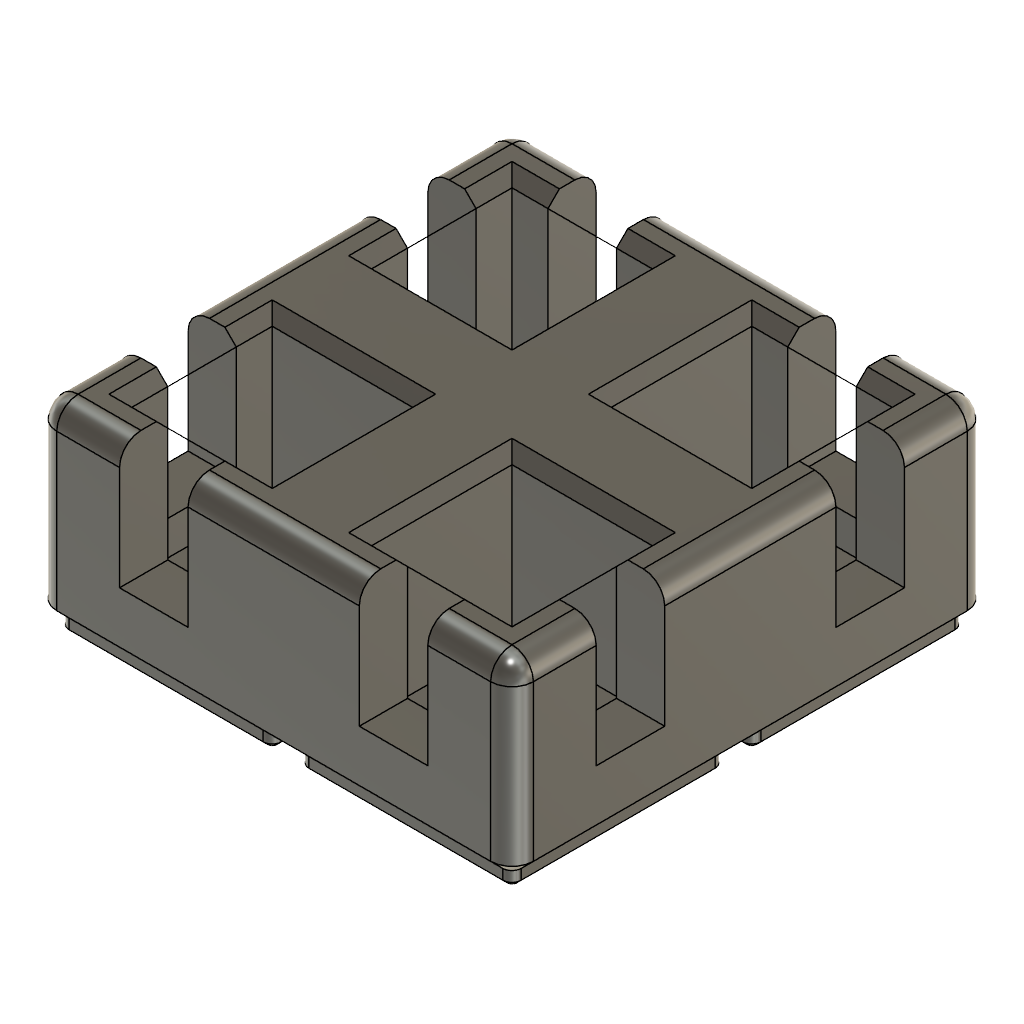
ready-parts-input-holder-v2 (Autodesk Fusion 360 design; units mm, degrees)
part number: 2026-10-03-11-04-50-135
Autodesk Fusion 360 part; units mm, degrees
sketch "Sketch_OuterProfile" plane through (0, 0, 0) normal (0, 0, 1) x (1, 0, 0)
  line L0 (41.75, 41.75) -> (-41.75, 41.75)
  line L1 (-41.75, 41.75) -> (-41.75, -41.75)
  line L2 (-41.75, -41.75) -> (41.75, -41.75)
  line L3 (41.75, -41.75) -> (41.75, 41.75)
  line L4 (41.75, 41.75) -> (-41.75, -41.75) construction
  dimension "d24" = 83.5
  dimension "d25" = 83.5
  constraint midpoint origin L4
  measures "d24" horizontal distance of L0.start L0.end
  measures "d25" vertical distance of L0.end L1.end
extrude "Extrude_Body" add sketch "Sketch_OuterProfile" along normal blind 31
fillet "Fillet_OuterVerticalEdges" radius 3.75 4 edges at (41.75, -41.75, 15.5) (-41.75, -41.75, 15.5) (-41.75, 41.75, 15.5) (41.75, 41.75, 15.5)
fillet "Fillet_TopOuterEdge" radius 3.75 64 edges at (40.6517, 40.6517, 31) (41.75, 0, 31) (40.6517, -40.6517, 31) (0, -41.75, 31) (-40.6517, -40.6517, 31) (-41.75, 0, 31) (-40.6517, 40.6517, 31) (0, 41.75, 31) (0, 41.75, 31) (-40.6517, 40.6517, 31) (-41.75, 0, 31) (-40.6517, -40.6517, 31) (0, -41.75, 31) (40.6517, -40.6517, 31) (41.75, 0, 31) (40.6517, 40.6517, 31) (-40.6517, 40.6517, 31) (0, 41.75, 31) (40.6517, 40.6517, 31) (41.75, 0, 31) (40.6517, -40.6517, 31) (0, -41.75, 31) (-40.6517, -40.6517, 31) (-41.75, 0, 31) (-41.75, 0, 31) (-40.6517, -40.6517, 31) (0, -41.75, 31) (40.6517, -40.6517, 31) (41.75, 0, 31) (40.6517, 40.6517, 31) (0, 41.75, 31) (-40.6517, 40.6517, 31) (-40.6517, -40.6517, 31) (-41.75, 0, 31) (-40.6517, 40.6517, 31) (0, 41.75, 31) (40.6517, 40.6517, 31) (41.75, 0, 31) (40.6517, -40.6517, 31) (0, -41.75, 31) (0, -41.75, 31) (40.6517, -40.6517, 31) (41.75, 0, 31) (40.6517, 40.6517, 31) (0, 41.75, 31) (-40.6517, 40.6517, 31) (-41.75, 0, 31) (-40.6517, -40.6517, 31) (40.6517, -40.6517, 31) (0, -41.75, 31) (-40.6517, -40.6517, 31) (-41.75, 0, 31) (-40.6517, 40.6517, 31) (0, 41.75, 31) (40.6517, 40.6517, 31) (41.75, 0, 31) (41.75, 0, 31) (40.6517, 40.6517, 31) (0, 41.75, 31) (-40.6517, 40.6517, 31) (-41.75, 0, 31) (-40.6517, -40.6517, 31) (0, -41.75, 31) (40.6517, -40.6517, 31)
ref_plane "WorkPlane1" through (0, 0, 11) normal (0, 0, 1) x (1, 0, 0)
sketch "Sketch_Pocket_1" plane through (0, 0, 11) normal (0, 0, 1) x (1, 0, 0)
  line L0 (-8.7, -8.7) -> (-33.3, -8.7)
  line L1 (-33.3, -8.7) -> (-33.3, -33.3)
  line L2 (-33.3, -33.3) -> (-8.7, -33.3)
  line L3 (-8.7, -33.3) -> (-8.7, -8.7)
  dimension "d35" = 24.6
  dimension "d36" = 24.6
  measures "d35" horizontal distance of L0.start L0.end
  measures "d36" vertical distance of L0.end L1.end
extrude "Extrude_Pocket_1" cut sketch "Sketch_Pocket_1" along normal blind -8 and the other way blind -25
sketch "Sketch_Pocket_2" plane through (0, 0, 11) normal (0, 0, 1) x (1, 0, 0)
  line L0 (-8.7, 33.3) -> (-33.3, 33.3)
  line L1 (-33.3, 33.3) -> (-33.3, 8.7)
  line L2 (-33.3, 8.7) -> (-8.7, 8.7)
  line L3 (-8.7, 8.7) -> (-8.7, 33.3)
  dimension "d39" = 24.6
  dimension "d40" = 24.6
  measures "d39" horizontal distance of L0.start L0.end
  measures "d40" vertical distance of L0.end L1.end
extrude "Extrude_Pocket_2" cut sketch "Sketch_Pocket_2" along normal blind -8 and the other way blind -45
sketch "Sketch_Pocket_3" plane through (0, 0, 11) normal (0, 0, 1) x (1, 0, 0)
  line L0 (33.3, -8.7) -> (8.7, -8.7)
  line L1 (8.7, -8.7) -> (8.7, -33.3)
  line L2 (8.7, -33.3) -> (33.3, -33.3)
  line L3 (33.3, -33.3) -> (33.3, -8.7)
  dimension "d43" = 24.6
  dimension "d44" = 24.6
  measures "d43" horizontal distance of L0.start L0.end
  measures "d44" vertical distance of L0.end L1.end
extrude "Extrude_Pocket_3" cut sketch "Sketch_Pocket_3" along normal blind -8 and the other way blind -42
sketch "Sketch_Pocket_4" plane through (0, 0, 11) normal (0, 0, 1) x (1, 0, 0)
  line L0 (33.3, 33.3) -> (8.7, 33.3)
  line L1 (8.7, 33.3) -> (8.7, 8.7)
  line L2 (8.7, 8.7) -> (33.3, 8.7)
  line L3 (33.3, 8.7) -> (33.3, 33.3)
  dimension "d47" = 24.6
  dimension "d48" = 24.6
  measures "d47" horizontal distance of L0.start L0.end
  measures "d48" vertical distance of L0.end L1.end
extrude "Extrude_Pocket_4" cut sketch "Sketch_Pocket_4" along normal blind -8 and the other way blind -38
chamfer "Chamfer_PocketEdges" distance 2 angle 45 12 edges at (33.3, 21, 31) (8.7, 21, 31) (21, 33.3, 31) (33.3, -21, 31) (8.7, -21, 31) (21, -8.7, 31) (-8.7, 21, 31) (-33.3, 21, 31) (-21, 33.3, 31) (-8.7, -21, 31) (-33.3, -21, 31) (-21, -8.7, 31) tangent chain off
chamfer "Chamfer_PocketEdges" distance 2 angle 45 4 edges at (21, -33.3, 31) (-21, -33.3, 31) (-21, 8.7, 31) (21, 8.7, 31) tangent chain off
sketch "Sketch_Foot_1" plane through (0, 0, 0) normal (0, 0, 1) x (1, 0, 0)
  line L0 (-3.01, -3.01) -> (-38.99, -3.01)
  line L1 (-38.99, -3.01) -> (-38.99, -38.99)
  line L2 (-38.99, -38.99) -> (-3.01, -38.99)
  line L3 (-3.01, -38.99) -> (-3.01, -3.01)
  dimension "d61" = 35.98
  dimension "d62" = 35.98
  measures "d61" horizontal distance of L0.start L0.end
  measures "d62" vertical distance of L0.end L1.end
extrude "Extrude_Foot_1" [suppressed]
fillet "Fillet_FootEdges_1" [suppressed]
sketch "Sketch_Foot_2" plane through (0, 0, 0) normal (0, 0, 1) x (1, 0, 0)
  line L0 (-3.01, 38.99) -> (-38.99, 38.99)
  line L1 (-38.99, 38.99) -> (-38.99, 3.01)
  line L2 (-38.99, 3.01) -> (-3.01, 3.01)
  line L3 (-3.01, 3.01) -> (-3.01, 38.99)
  dimension "d67" = 35.98
  dimension "d68" = 35.98
  measures "d67" horizontal distance of L0.start L0.end
  measures "d68" vertical distance of L0.end L1.end
extrude "Extrude_Foot_2" [suppressed]
fillet "Fillet_FootEdges_2" [suppressed]
sketch "Sketch_Foot_3" plane through (0, 0, 0) normal (0, 0, 1) x (1, 0, 0)
  line L0 (38.99, -3.01) -> (3.01, -3.01)
  line L1 (3.01, -3.01) -> (3.01, -38.99)
  line L2 (3.01, -38.99) -> (38.99, -38.99)
  line L3 (38.99, -38.99) -> (38.99, -3.01)
  dimension "d73" = 35.98
  dimension "d74" = 35.98
  measures "d73" horizontal distance of L0.start L0.end
  measures "d74" vertical distance of L0.end L1.end
extrude "Extrude_Foot_3" [suppressed]
fillet "Fillet_FootEdges_3" [suppressed]
sketch "Sketch_Foot_4" plane through (0, 0, 0) normal (0, 0, 1) x (1, 0, 0)
  line L0 (38.99, 38.99) -> (3.01, 38.99)
  line L1 (3.01, 38.99) -> (3.01, 3.01)
  line L2 (3.01, 3.01) -> (38.99, 3.01)
  line L3 (38.99, 3.01) -> (38.99, 38.99)
  dimension "d79" = 35.98
  dimension "d80" = 35.98
  measures "d79" horizontal distance of L0.start L0.end
  measures "d80" vertical distance of L0.end L1.end
extrude "Extrude_Foot_4" [suppressed]
fillet "Fillet_FootEdges_4" [suppressed]
extrude "Extrude10" [suppressed]
ref_plane "WorkPlane2" through (0, 0, 0) normal (0, 0, 1) x (1, 0, 0)
sketch "gf_std_foot1" plane through (0, 0, 0) normal (0, 0, 1) x (1, 0, 0)
  line L0 (-4, -0.25) -> (-38, -0.25)
  line L1 (-41.75, -4) -> (-41.75, -38)
  line L2 (-38, -41.75) -> (-4, -41.75)
  line L3 (-0.25, -38) -> (-0.25, -4)
  arc A0 (-38, -0.25) -> (-41.75, -4) centre (-38, -4) ccw
  arc A1 (-41.75, -38) -> (-38, -41.75) centre (-38, -38) ccw
  arc A2 (-4, -41.75) -> (-0.25, -38) centre (-4, -38) ccw
  arc A3 (-0.25, -4) -> (-4, -0.25) centre (-4, -4) ccw
  line L4 (-4, 41.75) -> (-38, 41.75)
  line L5 (-41.75, 38) -> (-41.75, 4)
  line L6 (-38, 0.25) -> (-4, 0.25)
  line L7 (-0.25, 4) -> (-0.25, 38)
  arc A4 (-38, 41.75) -> (-41.75, 38) centre (-38, 38) ccw
  arc A5 (-41.75, 4) -> (-38, 0.25) centre (-38, 4) ccw
  arc A6 (-4, 0.25) -> (-0.25, 4) centre (-4, 4) ccw
  arc A7 (-0.25, 38) -> (-4, 41.75) centre (-4, 38) ccw
  line L8 (38, -0.25) -> (4, -0.25)
  line L9 (0.25, -4) -> (0.25, -38)
  line L10 (4, -41.75) -> (38, -41.75)
  line L11 (41.75, -38) -> (41.75, -4)
  arc A8 (4, -0.25) -> (0.25, -4) centre (4, -4) ccw
  arc A9 (0.25, -38) -> (4, -41.75) centre (4, -38) ccw
  arc A10 (38, -41.75) -> (41.75, -38) centre (38, -38) ccw
  arc A11 (41.75, -4) -> (38, -0.25) centre (38, -4) ccw
  line L12 (38, 41.75) -> (4, 41.75)
  line L13 (0.25, 38) -> (0.25, 4)
  line L14 (4, 0.25) -> (38, 0.25)
  line L15 (41.75, 4) -> (41.75, 38)
  arc A12 (4, 41.75) -> (0.25, 38) centre (4, 38) ccw
  arc A13 (0.25, 4) -> (4, 0.25) centre (4, 4) ccw
  arc A14 (38, 0.25) -> (41.75, 4) centre (38, 4) ccw
  arc A15 (41.75, 38) -> (38, 41.75) centre (38, 38) ccw
  constraint tangent L0 A0
  constraint tangent L1 A0
  constraint tangent L1 A1
  constraint tangent L2 A1
  constraint tangent L2 A2
  constraint tangent L3 A2
  constraint tangent L3 A3
  constraint tangent L0 A3
  constraint tangent L4 A4
  constraint tangent L5 A4
  constraint tangent L5 A5
  constraint tangent L6 A5
  constraint tangent L6 A6
  constraint tangent L7 A6
  constraint tangent L7 A7
  constraint tangent L4 A7
  constraint tangent L8 A8
  constraint tangent L9 A8
  constraint tangent L9 A9
  constraint tangent L10 A9
  constraint tangent L10 A10
  constraint tangent L11 A10
  constraint tangent L11 A11
  constraint tangent L8 A11
  constraint tangent L12 A12
  constraint tangent L13 A12
  constraint tangent L13 A13
  constraint tangent L14 A13
  constraint tangent L14 A14
  constraint tangent L15 A14
  constraint tangent L15 A15
  constraint tangent L12 A15
extrude "gf_std_foot1 (1)" add sketch "gf_std_foot1" against normal blind 2.15 draft -45
ref_plane "WorkPlane3" through (0, 0, -2.15) normal (0, 0, 1) x (1, 0, 0)
sketch "gf_std_foot2" plane through (0, 0, -2.15) normal (0, 0, 1) x (1, 0, 0)
  line L0 (-4, -2.4) -> (-38, -2.4)
  line L1 (-39.6, -4) -> (-39.6, -38)
  line L2 (-38, -39.6) -> (-4, -39.6)
  line L3 (-2.4, -38) -> (-2.4, -4)
  arc A0 (-38, -2.4) -> (-39.6, -4) centre (-38, -4) ccw
  arc A1 (-39.6, -38) -> (-38, -39.6) centre (-38, -38) ccw
  arc A2 (-4, -39.6) -> (-2.4, -38) centre (-4, -38) ccw
  arc A3 (-2.4, -4) -> (-4, -2.4) centre (-4, -4) ccw
  line L4 (-4, 39.6) -> (-38, 39.6)
  line L5 (-39.6, 38) -> (-39.6, 4)
  line L6 (-38, 2.4) -> (-4, 2.4)
  line L7 (-2.4, 4) -> (-2.4, 38)
  arc A4 (-38, 39.6) -> (-39.6, 38) centre (-38, 38) ccw
  arc A5 (-39.6, 4) -> (-38, 2.4) centre (-38, 4) ccw
  arc A6 (-4, 2.4) -> (-2.4, 4) centre (-4, 4) ccw
  arc A7 (-2.4, 38) -> (-4, 39.6) centre (-4, 38) ccw
  line L8 (38, -2.4) -> (4, -2.4)
  line L9 (2.4, -4) -> (2.4, -38)
  line L10 (4, -39.6) -> (38, -39.6)
  line L11 (39.6, -38) -> (39.6, -4)
  arc A8 (4, -2.4) -> (2.4, -4) centre (4, -4) ccw
  arc A9 (2.4, -38) -> (4, -39.6) centre (4, -38) ccw
  arc A10 (38, -39.6) -> (39.6, -38) centre (38, -38) ccw
  arc A11 (39.6, -4) -> (38, -2.4) centre (38, -4) ccw
  line L12 (38, 39.6) -> (4, 39.6)
  line L13 (2.4, 38) -> (2.4, 4)
  line L14 (4, 2.4) -> (38, 2.4)
  line L15 (39.6, 4) -> (39.6, 38)
  arc A12 (4, 39.6) -> (2.4, 38) centre (4, 38) ccw
  arc A13 (2.4, 4) -> (4, 2.4) centre (4, 4) ccw
  arc A14 (38, 2.4) -> (39.6, 4) centre (38, 4) ccw
  arc A15 (39.6, 38) -> (38, 39.6) centre (38, 38) ccw
  constraint tangent L0 A0
  constraint tangent L1 A0
  constraint tangent L1 A1
  constraint tangent L2 A1
  constraint tangent L2 A2
  constraint tangent L3 A2
  constraint tangent L3 A3
  constraint tangent L0 A3
  constraint tangent L4 A4
  constraint tangent L5 A4
  constraint tangent L5 A5
  constraint tangent L6 A5
  constraint tangent L6 A6
  constraint tangent L7 A6
  constraint tangent L7 A7
  constraint tangent L4 A7
  constraint tangent L8 A8
  constraint tangent L9 A8
  constraint tangent L9 A9
  constraint tangent L10 A9
  constraint tangent L10 A10
  constraint tangent L11 A10
  constraint tangent L11 A11
  constraint tangent L8 A11
  constraint tangent L12 A12
  constraint tangent L13 A12
  constraint tangent L13 A13
  constraint tangent L14 A13
  constraint tangent L14 A14
  constraint tangent L15 A14
  constraint tangent L15 A15
  constraint tangent L12 A15
extrude "gf_std_foot2 (1)" add sketch "gf_std_foot2" against normal blind 1.8
ref_plane "WorkPlane4" through (0, 0, -3.95) normal (0, 0, 1) x (1, 0, 0)
sketch "gf_std_foot3" plane through (0, 0, -3.95) normal (0, 0, 1) x (1, 0, 0)
  line L0 (-4, -2.4) -> (-38, -2.4)
  line L1 (-39.6, -4) -> (-39.6, -38)
  line L2 (-38, -39.6) -> (-4, -39.6)
  line L3 (-2.4, -38) -> (-2.4, -4)
  arc A0 (-38, -2.4) -> (-39.6, -4) centre (-38, -4) ccw
  arc A1 (-39.6, -38) -> (-38, -39.6) centre (-38, -38) ccw
  arc A2 (-4, -39.6) -> (-2.4, -38) centre (-4, -38) ccw
  arc A3 (-2.4, -4) -> (-4, -2.4) centre (-4, -4) ccw
  line L4 (-4, 39.6) -> (-38, 39.6)
  line L5 (-39.6, 38) -> (-39.6, 4)
  line L6 (-38, 2.4) -> (-4, 2.4)
  line L7 (-2.4, 4) -> (-2.4, 38)
  arc A4 (-38, 39.6) -> (-39.6, 38) centre (-38, 38) ccw
  arc A5 (-39.6, 4) -> (-38, 2.4) centre (-38, 4) ccw
  arc A6 (-4, 2.4) -> (-2.4, 4) centre (-4, 4) ccw
  arc A7 (-2.4, 38) -> (-4, 39.6) centre (-4, 38) ccw
  line L8 (38, -2.4) -> (4, -2.4)
  line L9 (2.4, -4) -> (2.4, -38)
  line L10 (4, -39.6) -> (38, -39.6)
  line L11 (39.6, -38) -> (39.6, -4)
  arc A8 (4, -2.4) -> (2.4, -4) centre (4, -4) ccw
  arc A9 (2.4, -38) -> (4, -39.6) centre (4, -38) ccw
  arc A10 (38, -39.6) -> (39.6, -38) centre (38, -38) ccw
  arc A11 (39.6, -4) -> (38, -2.4) centre (38, -4) ccw
  line L12 (38, 39.6) -> (4, 39.6)
  line L13 (2.4, 38) -> (2.4, 4)
  line L14 (4, 2.4) -> (38, 2.4)
  line L15 (39.6, 4) -> (39.6, 38)
  arc A12 (4, 39.6) -> (2.4, 38) centre (4, 38) ccw
  arc A13 (2.4, 4) -> (4, 2.4) centre (4, 4) ccw
  arc A14 (38, 2.4) -> (39.6, 4) centre (38, 4) ccw
  arc A15 (39.6, 38) -> (38, 39.6) centre (38, 38) ccw
  constraint tangent L0 A0
  constraint tangent L1 A0
  constraint tangent L1 A1
  constraint tangent L2 A1
  constraint tangent L2 A2
  constraint tangent L3 A2
  constraint tangent L3 A3
  constraint tangent L0 A3
  constraint tangent L4 A4
  constraint tangent L5 A4
  constraint tangent L5 A5
  constraint tangent L6 A5
  constraint tangent L6 A6
  constraint tangent L7 A6
  constraint tangent L7 A7
  constraint tangent L4 A7
  constraint tangent L8 A8
  constraint tangent L9 A8
  constraint tangent L9 A9
  constraint tangent L10 A9
  constraint tangent L10 A10
  constraint tangent L11 A10
  constraint tangent L11 A11
  constraint tangent L8 A11
  constraint tangent L12 A12
  constraint tangent L13 A12
  constraint tangent L13 A13
  constraint tangent L14 A13
  constraint tangent L14 A14
  constraint tangent L15 A14
  constraint tangent L15 A15
  constraint tangent L12 A15
extrude "gf_std_foot3 (1)" add sketch "gf_std_foot3" against normal blind 0.8 draft -45
ref_plane "WorkPlane5" through (0, 0, 9) normal (0, 0, 1) x (1, 0, 0)
sketch "Sketch_FingerNotches" plane through (0, 0, 9) normal (0, 0, 1) x (1, 0, 0)
  circle A0 centre (-33.3, -21) radius 6
  circle A1 centre (-21, -33.3) radius 6
  circle A2 centre (-33.3, 21) radius 6
  circle A3 centre (-21, 33.3) radius 6
  circle A4 centre (33.3, -21) radius 6
  circle A5 centre (21, -33.3) radius 6
  circle A6 centre (33.3, 21) radius 6
  circle A7 centre (21, 33.3) radius 6
extrude "Extrude_FingerNotches" cut sketch "Sketch_FingerNotches" along normal blind 23
ref_plane "WorkPlane6" through (0, 0, 9) normal (0, 0, 1) x (1, 0, 0)
sketch "Sketch_FingerSlots" plane through (0, 0, 9) normal (0, 0, 1) x (1, 0, 0)
  line L0 (-33.3, -27) -> (-45, -27)
  line L1 (-45, -27) -> (-45, -15)
  line L2 (-45, -15) -> (-33.3, -15)
  line L3 (-33.3, -15) -> (-33.3, -27)
  line L4 (-27, -33.3) -> (-15, -33.3)
  line L5 (-15, -33.3) -> (-15, -45)
  line L6 (-15, -45) -> (-27, -45)
  line L7 (-27, -45) -> (-27, -33.3)
  line L8 (-33.3, 15) -> (-45, 15)
  line L9 (-45, 15) -> (-45, 27)
  line L10 (-45, 27) -> (-33.3, 27)
  line L11 (-33.3, 27) -> (-33.3, 15)
  line L12 (-27, 33.3) -> (-15, 33.3)
  line L13 (-15, 33.3) -> (-15, 45)
  line L14 (-15, 45) -> (-27, 45)
  line L15 (-27, 45) -> (-27, 33.3)
  line L16 (33.3, -27) -> (45, -27)
  line L17 (45, -27) -> (45, -15)
  line L18 (45, -15) -> (33.3, -15)
  line L19 (33.3, -15) -> (33.3, -27)
  line L20 (15, -33.3) -> (27, -33.3)
  line L21 (27, -33.3) -> (27, -45)
  line L22 (27, -45) -> (15, -45)
  line L23 (15, -45) -> (15, -33.3)
  line L24 (33.3, 15) -> (45, 15)
  line L25 (45, 15) -> (45, 27)
  line L26 (45, 27) -> (33.3, 27)
  line L27 (33.3, 27) -> (33.3, 15)
  line L28 (15, 33.3) -> (27, 33.3)
  line L29 (27, 33.3) -> (27, 45)
  line L30 (27, 45) -> (15, 45)
  line L31 (15, 45) -> (15, 33.3)
extrude "Extrude_FingerSlots" cut sketch "Sketch_FingerSlots" along normal blind 23
equation "grid_pitch = 42 mm" comment "Gridfinity grid pitch (standard, per MG400 rig doc)"
equation "grid_clearance = 0.3 mm" comment "Fit clearance measured in Lab 1 (range 0.2-0.4 mm, chosen 0.3 mm)"
equation "gf_outer_offset = 0.5 mm" comment "Standard Gridfinity outer undersize per cell (42n - 0.5)"
equation "gf_corner_radius = 3.75 mm" comment "Standard Gridfinity outer corner radius"
equation "gf_foot_chamfer_bottom = 0.8 mm" comment "Gridfinity foot: bottom 45deg segment height (reference)"
equation "gf_foot_vertical = 1.8 mm" comment "Gridfinity foot: vertical segment height (reference)"
equation "gf_foot_chamfer_top = 2.15 mm" comment "Gridfinity foot: top 45deg segment height (reference)"
equation "foot_lead_in_chamfer = gf_foot_chamfer_bottom + gf_foot_chamfer_top" comment "Simplified single lead-in chamfer approximating the Gridfinity foot flare"
equation "grid_cols = 2" comment "Number of Gridfinity cells in X (build-time layout parameter)"
equation "grid_rows = 2" comment "Number of Gridfinity cells in Y (build-time layout parameter)"
equation "atom_width = 24.0 mm" comment "M5Stack AtomS3 official width (SKU C123)"
equation "atom_length = 24.0 mm" comment "M5Stack AtomS3 official length (SKU C123)"
equation "atom_height = 12.9 mm" comment "M5Stack AtomS3 official height (SKU C123)"
equation "part_clearance = 0.3 mm" comment "Printer fit clearance measured in Lab 1, applied per side between AtomS3 and pocket"
equation "pocket_width = atom_width + 2 * part_clearance" comment "Pocket opening width (AtomS3 width plus clearance both sides)"
equation "pocket_length = atom_length + 2 * part_clearance" comment "Pocket opening length (AtomS3 length plus clearance both sides)"
equation "pocket_depth = 8 mm" comment "ASSUMPTION: pocket depth, not specified by user; leaves part protruding for grip/suction access"
equation "lead_in_chamfer = 1 mm" comment "Standard chamfer on 3 sides of each pocket opening, aids insertion"
equation "key_edge_chamfer = lead_in_chamfer * 2" comment "Larger chamfer on one marked edge of each pocket: orientation key + extra finger access"
equation "floor_thickness = 3 mm" comment "ASSUMPTION: solid floor thickness beneath pockets, not specified by user"
equation "holder_height = pocket_depth + floor_thickness" comment "Total external height of the holder"
equation "holder_outer_x = grid_pitch * grid_cols - gf_outer_offset" comment "Standard Gridfinity outer size 42n - 0.5 (v2; v1 also subtracted grid_clearance -> 83.2)"
equation "holder_outer_y = grid_pitch * grid_rows - gf_outer_offset" comment "Standard Gridfinity outer size 42n - 0.5 (v2; v1 also subtracted grid_clearance -> 83.2)"
equation "d24 = holder_outer_x"
equation "d25 = holder_outer_y"
equation "d29 = gf_corner_radius"
equation "d32 = gf_corner_radius"
equation "d33 = holder_height"
equation "d35 = pocket_width"
equation "d36 = pocket_length"
equation "d37 = -pocket_depth"
equation "d39 = pocket_width"
equation "d40 = pocket_length"
equation "d41 = -pocket_depth"
equation "d43 = pocket_width"
equation "d44 = pocket_length"
equation "d45 = -pocket_depth"
equation "d47 = pocket_width"
equation "d48 = pocket_length"
equation "d49 = -pocket_depth"
equation "gf_socket_mouth_size = 41.98 mm" comment "v1 straight foot, NOT USED in v2 (suppressed). MEASURED from MG400 rakis grid_pos_0: top opening of real baseplate socket"
equation "gf_socket_mid_size = 37.68 mm" comment "v1 straight foot, NOT USED in v2 (suppressed). MEASURED: socket width after top chamfer segment"
equation "gf_socket_floor_size = 36.28 mm" comment "v1 straight foot, NOT USED in v2 (suppressed). MEASURED: narrowest width at socket floor"
equation "gf_socket_depth = 4.65 mm" comment "v1 straight foot, NOT USED in v2 (suppressed). MEASURED: real socket depth (0.70 + 1.80 + 2.15 mm segments), corrects earlier 4.75 mm assumption"
equation "foot_size = gf_socket_floor_size - grid_clearance" comment "v1 straight foot, NOT USED in v2 (suppressed). Simplified constant-width foot sized to the socket floor (narrowest, guaranteed-fit) minus clearance"
equation "foot_depth = gf_socket_depth" comment "v1 straight foot, NOT USED in v2 (suppressed). Foot protrusion depth below the main floor, matches measured socket depth"
equation "foot_corner_radius = 0.5 mm" comment "v1 straight foot, NOT USED in v2 (suppressed). MEASURED (approx): real socket corner radius near its narrowest point"
equation "total_height_with_feet = holder_height + 4.75 mm" comment "Overall height with the standard 4.75 mm Gridfinity foot"
equation "d61 = foot_size"
equation "d62 = foot_size"
equation "d63 = -foot_depth"
equation "d66 = foot_corner_radius"
equation "d67 = foot_size"
equation "d68 = foot_size"
equation "d69 = -foot_depth"
equation "d72 = foot_corner_radius"
equation "d73 = foot_size"
equation "d74 = foot_size"
equation "d75 = -foot_depth"
equation "d78 = foot_corner_radius"
equation "d79 = foot_size"
equation "d80 = foot_size"
equation "d81 = -foot_depth"
equation "d84 = foot_corner_radius"
equation "gf_fit_adjust = 0 mm" comment "Extra inward offset of the standard Gridfinity foot per side (0 = standard)"
equation "finger_cutout_radius = 6 mm" comment "Finger notch radius, as on the glass input holder"
equation "finger_cutout_floor = 6 mm" comment "Notch stops this high above the pocket floor: the lower wall still locates the part"
named bodies: "ready-parts-input-holder-v2"
